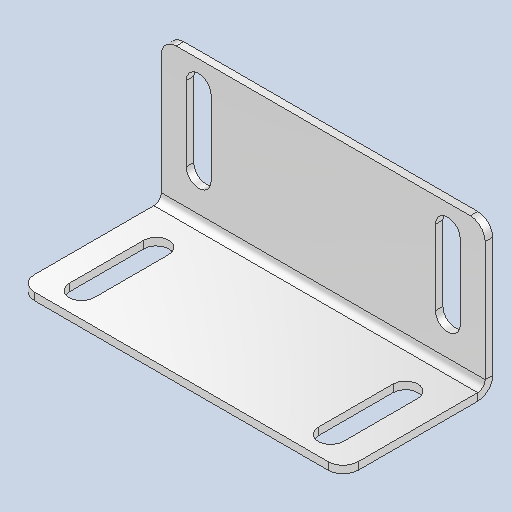
# Autodesk Inventor part: DMF-4005 Bed Bow Mount
Saved by Autodesk Inventor 2026.2 (Build 302298000, 298)
## iProperties
Created: 2024-04-28
Part Number: DMF-4005 Bed Bow Mount
Material: Stainless Steel AISI 304
Document SubType Name: Sheet Metal
Designer: pokla
Stock Number: DMF-4005
Density: 8 g/cm^3
Sheet Metal Rule: Default
Sheet Metal Width: 114,786 mm
Sheet Metal Length: 130,000 mm
Sheet Metal Area: 14922,159 mm^2
Appearance: Chrome - Satin
Flat Pattern Width: 11.4786 cm
Flat Pattern Length: 13 cm
Flat Pattern Area: 149.222 cm^2
Author: pokla
Autodesk Inventor part; units mm, degrees
ref_plane "YZ Plane" through (0, 0, 0) normal (1, 0, 0) x (0, 1, 0)
ref_plane "XZ Plane" through (0, 0, 0) normal (0, 1, 0) x (-1, 0, 0)
sketch "Sketch12" plane through (0, 0, 0) normal (0, 0, 1) x (1, 0, 0)
  line L0 (-65, 60) -> (65, 60)
  line L1 (65, 60) -> (65, 0)
  line L2 (65, 0) -> (-65, 0)
  line L3 (-65, 0) -> (-65, 60)
  point P0 (0, 0)
  point P1 (0, 0)
  dimension "d79" = 130
  dimension "d80" = 60
  measures "d79" distance of L0.start L0.end
  measures "d80" distance of L2.end L0.start
extrude "Plate3" add sketch "Sketch12" along normal blind 3
sketch "Sketch13" plane through (0, 0, 3) normal (0, 0, 1) x (1, 0, 0)
  line L0 (-50, 50) -> (-50, 20) construction
  line L1 (-55, 50) -> (-55, 20)
  line L2 (-45, 20) -> (-45, 50)
  arc A0 (-45, 50) -> (-55, 50) centre (-50, 50) ccw
  arc A1 (-55, 20) -> (-45, 20) centre (-50, 20) ccw
  line L3 (50, 50) -> (50, 20) construction
  line L4 (45, 50) -> (45, 20)
  line L5 (55, 20) -> (55, 50)
  arc A2 (55, 50) -> (45, 50) centre (50, 50) ccw
  arc A3 (45, 20) -> (55, 20) centre (50, 20) ccw
  line L6 (0, 0) -> (0, 35) construction
  point P0 (-50, 35)
  point P1 (50, 35)
  dimension "d81" = 100
  dimension "d82" = 10
  dimension "d83" = 30
  dimension "d85" = 35
  constraints: 18 end point, 8 point on circle, 8 tangent, 4 centre point, 3 parallel, 2 midpoint, 2 vertical, 1 horizontal alignment, 3 other
  measures "d81" distance between parallel lines of L3 L0
  measures "d82" distance between parallel lines of L2 L1
  measures "d83" distance of L0.start L0.end
  measures "d85" distance of L6.start L6.end
extrude "Cut2" cut sketch "Sketch13" against normal blind 3
sketch "Sketch14" plane through (65, 3, 0) normal (0, -1, 0) x (1, 0, 0)
  line L0 (-130, 0) -> (0, 0)
  line L1 (0, 0) -> (0, 60)
  line L2 (0, 60) -> (-130, 60)
  line L3 (-130, 60) -> (-130, 0)
  constraints: 6 end point, 1 horizontal, 1 perpendicular, 1 vertical
edge flange "Flange1" height 60 angle 90 thickness 3 bend radius 3 thickness toward (0, -1, 0) relief tear relief width 3 relief depth 1.5 edges at (0, 0, 3) wall of the first edge with corners at (-65, 3, 0) (65, 3, 0) (65, 3, 60) (-65, 3, 60)
bend "Bend2"
corner "Corner2"
ref_plane "Work Plane1" through (-65, 3, 3) normal (0, 0.7071068, -0.7071068) x (-1, 0, 0)
mirror "Mirror2" about plane through (-65, 3, 3) normal (0, 0.7071068, -0.7071068) of "Cut2"
fillet "Corner Round2" radius 6 4 edges at (65, 1.5, 60) (65, 60, 1.5) (-65, 60, 1.5) (-65, 1.5, 60)
equation "\"d86\" = Thickness"
equation "\"d75\" = Thickness"
equation "\"d88\" = BendReliefWidth"
equation "\"d89\" = BendReliefDepth"
equation "\"d90\" = MinimumRemnant"
equation "\"d91\" = TransitionRadius"
equation "\"d92\" = d80"
equation "\"d94\" = BendRadius"
equation "\"d95\" = CornerReliefSize"
equation "\"d96\" = GapSize"
equation "\"d97\" = JacobiRadiusSize"
equation "\"BendRadius\" = Thickness"
equation "\"BendReliefWidth\" = Thickness"
equation "\"BendReliefDepth\" = 0.5 * Thickness"
equation "\"CornerReliefSize\" = 4 * Thickness"
equation "\"MinimumRemnant\" = 2 * Thickness"
equation "\"TransitionRadius\" = BendRadius"
equation "\"JacobiRadiusSize\" = BendRadius"
equation "\"GapSize\" = Thickness"
equation "\"Thickness\" = 3"
body "Solid4"
